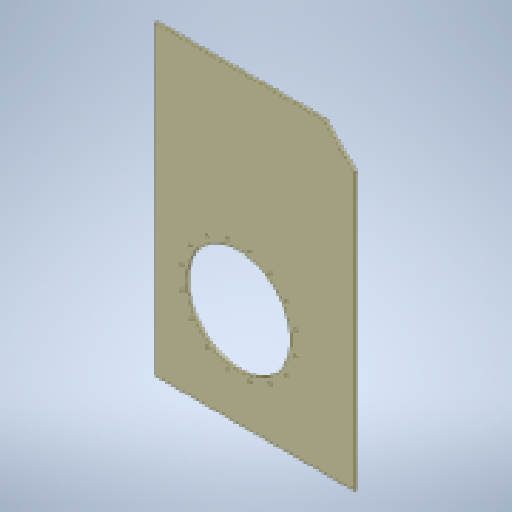
# Autodesk Inventor part: DMF-3013 Back Wall Dummy
Saved by Autodesk Inventor 2026.2 (Build 302298000, 298)
## iProperties
Created: 2023-08-31
Part Number: DMF-3013 Back Wall Dummy
Material: Polypropylene
Document SubType Name: Sheet Metal
Designer: admin
Stock Number: DMF-3013
Density: 0.899 g/cm^3
Flat Pattern Width: 92 cm
Flat Pattern Length: 141 cm
Flat Pattern Area: 12972 cm^2
Sheet Metal Rule: Default
Sheet Metal Width: 920,000 mm
Sheet Metal Length: 1410,000 mm
Sheet Metal Area: 1297200,000 mm^2
Appearance: Smooth - Ash
Author: admin
Autodesk Inventor part; units mm, degrees
ref_plane "YZ Plane" through (0, 0, 0) normal (1, 0, 0) x (0, 1, 0)
ref_plane "XZ Plane" through (0, 0, 0) normal (0, 1, 0) x (-1, 0, 0)
ref_plane "XY Plane" through (0, 0, 0) normal (0, 0, 1) x (1, 0, 0)
sketch "Sketch1" plane through (0, 0, 0) normal (0, 0, 1) x (1, 0, 0)
  line L0 (0, 0) -> (0, 1910) construction
  line L1 (395, 1910) -> (-445, 1910)
  line L2 (-445, 1910) -> (-1205, 1150)
  line L3 (-1205, 0) -> (-1205, 1150)
  line L4 (965, 0) -> (965, 1340)
  line L5 (395, 1910) -> (965, 1340)
  circle A0 centre (0, 953) radius 265 construction
  line L6 (965, 0) -> (-1205, 0)
  circle A1 centre (-825, 80) radius 55.5
  circle A2 centre (0, 953) radius 240
  line L7 (0, 1218) -> (0, 1193) construction
  circle A3 centre (51.6989, 1212.9081) radius 5.5
  line L8 (0, 953) -> (51.6989, 1212.9081) construction
  circle A4 centre (-51.6989, 1212.9081) radius 5.5
  circle A5 centre (-147.2261, 1173.3394) radius 5.5
  circle A6 centre (-220.3394, 1100.2261) radius 5.5
  circle A7 centre (-259.9081, 1004.6989) radius 5.5
  circle A8 centre (-259.9081, 901.3011) radius 5.5
  circle A9 centre (-220.3394, 805.7739) radius 5.5
  circle A10 centre (-147.2261, 732.6606) radius 5.5
  circle A11 centre (-51.6989, 693.0919) radius 5.5
  circle A12 centre (51.6989, 693.0919) radius 5.5
  circle A13 centre (147.2261, 732.6606) radius 5.5
  circle A14 centre (220.3394, 805.7739) radius 5.5
  circle A15 centre (259.9081, 901.3011) radius 5.5
  circle A16 centre (259.9081, 1004.6989) radius 5.5
  circle A17 centre (220.3394, 1100.2261) radius 5.5
  circle A18 centre (147.2261, 1173.3394) radius 5.5
  line L9 (-385, 1910) -> (-385, 500)
  line L10 (-385, 500) -> (535, 500)
  line L11 (535, 500) -> (535, 1770)
  dimension "d72" = 480
  dimension "d1" = 840
  dimension "d3" = 1150
  dimension "d12" = 1205
  dimension "d13" = 953
  dimension "d14" = 111
  dimension "d15" = 1910
  dimension "d34" = 380
  dimension "d35" = 80
  dimension "d37" = 2170
  dimension "d52" = 530
  dimension "d69" = 806.1017
  dimension "d71" = 1074.8023
  dimension "d74" = 11
  dimension "d79" = 11.25
  dimension "d82" = 360
  dimension "d84" = 430
  dimension "d85" = 500
  dimension "d86" = 820
  dimension "d88" = 135
  dimension "d89" = 135
  constraints: 24 end point, 18 centre point, 17 coincident, 7 point on line, 4 vertical, 2 horizontal, 2 perpendicular, 2 point on circle, 1 vertical alignment, 51 other
  measures "d1" distance of L1.start L1.end
  measures "d3" distance of L3.start L2.end
  measures "d12" distance from line of L3 A0.centre
  measures "d13" distance from line of L6 A0.centre
  measures "d14" diameter of A1
  measures "d15" vertical distance of L3.start L1.end
  measures "d34" distance from line of A1.centre L3
  measures "d35" distance from line of A1.centre L6
  measures "d37" distance between parallel lines of L4 L3
  measures "d52" diameter of A0
  measures "d69" distance of L1.start L4.end
  measures "d71" distance of L1.end L2.end
  measures "d74" diameter of A3
  measures "d79" angle of L0 L8
  measures "d84" distance between parallel lines of L4 L11
  measures "d85" distance between parallel lines of L6 L10
  measures "d86" distance between parallel lines of L3 L9
  measures "d88" angle of L2 L1
  measures "d89" angle of L1 L5
extrude "Plate1" add sketch "Sketch1" along normal blind 10 contours L5 L11 L10 L9 L1
body "Solid1"
